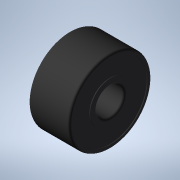
# Autodesk Inventor part: C-SE692ZZ
Saved by Autodesk Inventor 2021 (Build 250183000, 183)
## iProperties
Created: 2025-05-01
Part Number: C-SE692ZZ
Material: Generic
Catalog Web Link: www.cadenas.de
Description: C-SE___ZZ, C-SE___AZZ-Economy Stainless Miniature Deep Groove Ball Bearing - Double Shielded, Single Row
Vendor: MISUMI
Document SubType Name: Modeling
Designer: psAdmin
Manufacturer: MISUMI
Mass: 0.0735785 g
Surface Area: 1.25056 cm^2
Volume: 0.0735785 cm^3
Density: 1 g/cm^3
Appearance: PSOLRGB-175-175-175
Category: PARTsolutions
Company: MISUMI
Title: C-SE692ZZ
Author: Cadenas PARTsolutions
Comments: Economy Stainless Miniature Deep Groove Ball Bearing - Double Shielded, Single Row
PSOL_IDENT_0: {$CADENAS_DATA/23d-libs/misumi/metric/12_bearing_holders/c_se682zz.prj},174 {VTYP=3D},{NB=C-SE692ZZ}
PSOL_IDENT_1: ,{LINA=C-SE692ZZ},{NN=C-SE___ZZ, C-SE___AZZ},{DATE=29.05.2023 02:13:15},{GEOMDATE=25.05.2021 01:28:2
PSOL_IDENT_2: 4},{VERSION=},{LINEID=210},{WBVAR=},{WBNUMERIC=}  {NB=C-SE692ZZ},{LINA=C-SE692ZZ},{KT=DUMMY},{PN=C-S
PSOL_IDENT_3: E692ZZ},{TS=C-SE692ZZ},{DD=2.0},{D=6},{B=3.0},{RR=0.15},{A=2.9004},{BB=0.300},{C=0.500}
NB: C-SE692ZZ
NN: C-SE___ZZ, C-SE___AZZ
NT: Economy Stainless Miniature Deep Groove Ball Bearing - Double Shielded, Single Row
NBSYN: $PN.
LINA: C-SE692ZZ
CATALOG: Misumi
PN: C-SE692ZZ
TS: C-SE692ZZ
DD: 2
D: 6
B: 3
RR: 0.15
SUPPLIER: MISUMI
ARTICLENO: C-SE692ZZ
BOMINFO: C-SE692ZZ
CREATOR: CADENAS GmbH
Autodesk Inventor part; units mm, degrees
sketch "Sketch_1" plane through (0, 0, 0) normal (0, 0, 1) x (1, 0, 0)
  line L0 (2.85, 0) -> (0.15, 0)
  arc A0 (0, 1.15) -> (0.15, 1) centre (0.15, 1.15) ccw
  line L1 (0.15, 1) -> (2.85, 1)
  arc A1 (2.85, 1) -> (3, 1.15) centre (2.85, 1.15) ccw
  line L2 (3, 1.15) -> (3, 1.5)
  line L3 (3, 1.5) -> (2.9502, 1.5)
  line L4 (2.9502, 1.5) -> (2.9502, 2.7)
  line L5 (2.9502, 2.7) -> (3, 2.7)
  line L6 (3, 2.7) -> (3, 2.85)
  arc A2 (3, 2.85) -> (2.85, 3) centre (2.85, 2.85) ccw
  line L7 (2.85, 3) -> (0.15, 3)
  arc A3 (0.15, 3) -> (0, 2.85) centre (0.15, 2.85) ccw
  line L8 (0, 2.85) -> (0, 2.7)
  line L9 (0, 2.7) -> (0.0498, 2.7)
  line L10 (0.0498, 2.7) -> (0.0498, 1.5)
  line L11 (0.0498, 1.5) -> (0, 1.5)
  line L12 (0, 1.5) -> (0, 1.15)
  constraints: 26 end point, 8 point on circle, 4 centre point
revolve "Revolution1" add sketch "Sketch_1" angle 360 about axis through (2.85, 0, 0) along (1, 0, 0)
ref_plane "to_housing_XY" through (0, 0, 0) normal (1, 0, 0) x (0, 0, -1)
ref_plane "to_housing_YZ" through (0, 0, 0) normal (0, 0, -1) x (0, 1, 0)
ref_plane "to_housing_ZX" through (0, 0, 0) normal (0, 1, 0) x (1, 0, 0)
ref_plane "to_housing_center_XY" through (1.5, 0, 0) normal (1, 0, 0) x (0, 0, -1)
ref_plane "to_housing_center_YZ" through (1.5, 0, 0) normal (0, 0, -1) x (0, 1, 0)
ref_plane "to_housing_center_ZX" through (1.5, 0, 0) normal (0, 1, 0) x (1, 0, 0)
body "Solid1"
